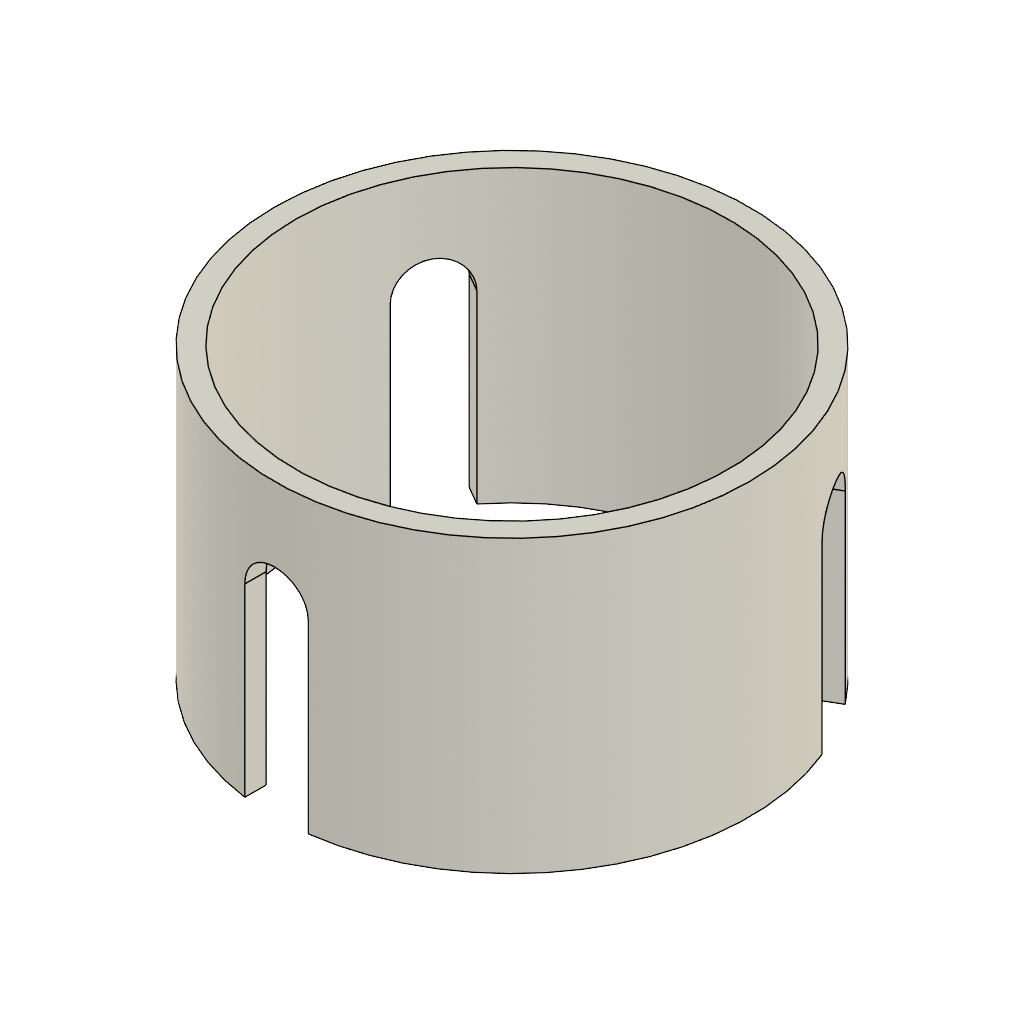
05-06 Floating ring (Autodesk Fusion 360 design; units mm, degrees)
Autodesk Fusion 360 part; units mm, degrees
sketch "Sketch1" plane through (0, 0, 0) normal (0, 0, 1) x (1, 0, 0)
  circle A0 centre (0, 0) radius 41
  circle A1 centre (0, 0) radius 45
  dimension "d1" = 4
  dimension "d2" = 82
  constraint coincident A0.centre A1.centre
  constraint concentric A0 A1
  measures "d1" distance of A0 A1
  measures "d2" diameter of A0
extrude "Extrude1" add sketch "Sketch1" along normal blind 55
sketch "Sketch3" plane through (0, 0, 0) normal (0, 1, 0) x (1, 0, 0)
  line L0 (6, 0) -> (6, -35)
  line L1 (-6, 0) -> (-6, -35)
  arc A0 (-6, -35) -> (6, -35) centre (0, -35) ccw
  line L2 (-6, 0) -> (6, 0)
  dimension "d5" = 35
  dimension "d6" = 6
  dimension "d7" = 12
  constraint vertical L0
  constraint vertical L1
  constraint equal L0 L1
  constraint tangent L1 A0
  constraint perpendicular L0 L2
  measures "d5" distance of L0.start L0.end
  measures "d6" distance of origin L0
  measures "d7" distance of L0 L1
extrude "Extrude2" cut sketch "Sketch3" against normal blind 70
pattern_circular "C-Pattern1" count 3 over 360 about axis through (0, 0, 1.75) along (0, 0, 1) of "Extrude2"
